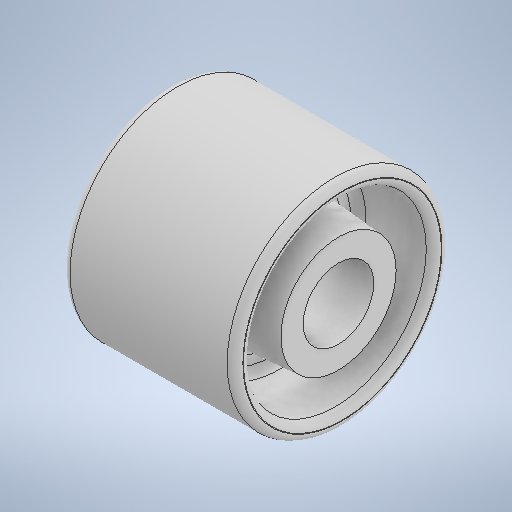
# Autodesk Inventor part: Polea
Saved by Autodesk Inventor 2025.3 (Build 293356030, 356C)
## iProperties
Created: 2025-08-17
Part Number: Polea
Material: Generic
Document SubType Name: Modeling
Designer: PC
Density: 1 g/cm^3
Appearance: Default
Author: PC
Autodesk Inventor part; units mm, degrees
ref_plane "YZ Plane" through (0, 0, 0) normal (1, 0, 0) x (0, 1, 0)
ref_plane "XZ Plane" through (0, 0, 0) normal (0, 1, 0) x (-1, 0, 0)
ref_plane "XY Plane" through (0, 0, 0) normal (0, 0, 1) x (1, 0, 0)
sketch "Sketch1" plane through (0, 0, 0) normal (0, 1, 0) x (-1, 0, 0)
  line L0 (0, 0) -> (0, -41) construction
  line L1 (0, -41) -> (-30, -41)
  line L2 (-33, -38) -> (-33, -37.786)
  line L3 (-30.2216, -34.7942) -> (-8.7784, -33.2058)
  line L4 (-6, -30.214) -> (-6, -26.7739)
  line L5 (-8.7654, -23.7831) -> (-31.5, -22)
  line L6 (-31.5, -22) -> (-31.5, -13.45)
  line L7 (-31.5, -13.45) -> (0, -13.45)
  line L8 (0, -41) -> (30, -41)
  line L9 (33, -38) -> (33, -37.786)
  line L10 (30.2216, -34.7942) -> (8.7784, -33.2058)
  line L11 (6, -30.214) -> (6, -26.7739)
  line L12 (8.7654, -23.7831) -> (31.5, -22)
  line L13 (31.5, -22) -> (31.5, -13.45)
  line L14 (31.5, -13.45) -> (0, -13.45)
  line L15 (0, 0) -> (44.8111, 0) construction
  arc A0 (30, -41) -> (33, -38) centre (30, -38) ccw
  arc A1 (33, -37.786) -> (30.2216, -34.7942) centre (30, -37.786) ccw
  arc A2 (6, -30.214) -> (8.7784, -33.2058) centre (9, -30.214) ccw
  arc A3 (8.7654, -23.7831) -> (6, -26.7739) centre (9, -26.7739) ccw
  arc A4 (-8.7784, -33.2058) -> (-6, -30.214) centre (-9, -30.214) ccw
  arc A5 (-6, -26.7739) -> (-8.7654, -23.7831) centre (-9, -26.7739) ccw
  arc A6 (-30.2216, -34.7942) -> (-33, -37.786) centre (-30, -37.786) ccw
  arc A7 (-33, -38) -> (-30, -41) centre (-30, -38) ccw
  point P0 (-33, -41)
  point P1 (-33, -35)
  point P2 (-6, -33)
  point P3 (-6, -24)
  point P4 (33, -41)
  point P5 (33, -35)
  point P6 (6, -33)
  point P7 (6, -24)
  dimension "d0" = 41
  dimension "d1" = 33
  dimension "d2" = 6
  dimension "d3" = 33
  dimension "d4" = 24
  dimension "d5" = 22
  dimension "d6" = 13.45
  dimension "d7" = 6
  dimension "d8" = 6
  dimension "d9" = 31.5
  dimension "d10" = 31.5
  dimension "d12" = 3
  constraints: 32 end point, 17 point on line, 16 point on circle, 16 tangent, 8 centre point, 7 equal radius, 6 symmetric about line, 2 horizontal, 2 vertical, 1 perpendicular
  measures "d0" distance of L0.start L0.end
  measures "d1" distance of L0.end point (-33, -41)
  measures "d2" distance of point (-33, -41) point (-33, -35)
  measures "d3" vertical distance of point (-6, -33) L0.start
  measures "d4" vertical distance of point (-6, -24) L0.start
  measures "d5" vertical distance of L5.end L0.start
  measures "d6" vertical distance of L6.end L0.start
  measures "d7" horizontal distance of L0.start point (-6, -33)
  measures "d8" horizontal distance of L0.start point (-6, -24)
  measures "d9" horizontal distance of L0.start L5.end
  measures "d10" horizontal distance of L0.start L6.end
  measures "d12" radius of A0
revolve "Revolution1" add sketch "Sketch1" angle 360 about axis through (0, 0, 0) along (-1, 0, 0)
equation "\"d8\" = d7"
equation "\"d10\" = d9"
body "Solid1"
